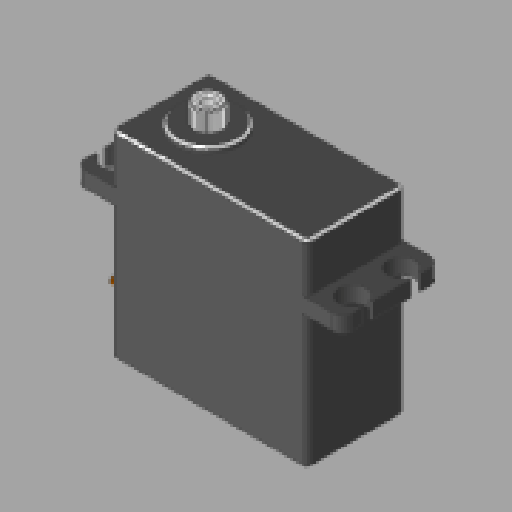
# Autodesk Inventor part: DSC55MG_HipServo
Saved by Autodesk Inventor 2025 (Build 290162000, 162)
## iProperties
Created: 2024-10-08
Part Number: DSC55MG_HipServo
Material: 일반
Document SubType Name: Modeling
Designer: OSB
Density: 2.16623 g/cm^3
Appearance: 기본값
Mass: 72 g
Surface Area: 73.8579 cm^2
Volume: 33.2375 cm^3
Author: OSB
Autodesk Inventor part; units mm, degrees
(part 1 of 2)
ref_plane "YZ Plane" through (0, 0, 0) normal (1, 0, 0) x (0, 1, 0)
ref_plane "XZ Plane" through (0, 0, 0) normal (0, 1, 0) x (-1, 0, 0)
ref_plane "XY Plane" through (0, 0, 0) normal (0, 0, 1) x (1, 0, 0)
sketch "스케치1" plane through (0, 0, 0) normal (0, 1, 0) x (-1, 0, 0)
  line L0 (0, 0) -> (40, 0)
  line L1 (40, 0) -> (40, -20)
  line L2 (40, -20) -> (0, -20)
  line L3 (0, -20) -> (0, 0)
  dimension "d0" = 40
  dimension "d1" = 20
  constraints: 8 end point, 2 parallel, 1 horizontal, 1 perpendicular
  measures "d0" distance of L1.end L2.end
  measures "d1" distance of L0.end L1.end
extrude "돌출1" add sketch "스케치1" along normal blind 40.5
sketch "스케치2" plane through (0, 40.5, 0) normal (0, 1, 0) x (1, 0, 0)
  line L0 (0, 20) -> (-40, 20) projected
  line L1 (-40, 20) -> (-40, 0) projected
  line L2 (-40, 0) -> (0, 0) projected
  line L3 (0, 0) -> (0, 20) projected
  circle A0 centre (-30.2, 10) radius 3
  circle A1 centre (-30.2, 10) radius 6.5
  point P0 (-40, 10)
  dimension "d4" = 9.8
  dimension "d5" = 6
  dimension "d6" = 13
  constraints: 2 centre point, 1 coincident, 1 horizontal alignment, 1 midpoint
  measures "d4" distance from line of L1 A0.centre
  measures "d5" diameter of A0
  measures "d6" diameter of A1
extrude "돌출2" add sketch "스케치2" along normal blind 1.2 contours A1
extrude "돌출3" add sketch "스케치2" along normal blind 5 contours A0
sketch "스케치3" plane through (-40, 0, 0) normal (0, 0, 1) x (1, 0, 0)
  line L0 (0, 0) -> (40, 0) projected
  line L1 (40, 0) -> (40, 40.5) projected
  line L2 (0, 40.5) -> (40, 40.5) projected
  line L3 (0, 0) -> (0, 40.5) projected
  line L4 (-7.25, 30.5) -> (47.25, 30.5)
  line L5 (47.25, 30.5) -> (47.25, 27.3)
  line L6 (47.25, 27.3) -> (-7.25, 27.3)
  line L7 (-7.25, 27.3) -> (-7.25, 30.5)
  line L8 (0, 0) -> (40, 0) projected
  point P0 (20, 0)
  point P1 (20, 0)
  point P2 (40, 30.5)
  point P3 (40, 27.3)
  point P4 (0, 27.3)
  point P5 (0, 30.5)
  dimension "d11" = 27.3
  dimension "d12" = 3.2
  dimension "d13" = 27.25
  dimension "d14" = 27.25
  constraints: 8 end point, 2 midpoint, 2 parallel, 1 horizontal, 1 perpendicular
  measures "d11" distance between parallel lines of L0 L6
  measures "d12" distance between parallel lines of L6 L4
  measures "d13" distance from line of point (20, 0) L7
  measures "d14" distance from line of L5 point (20, 0)
extrude "돌출4" add sketch "스케치3" against normal up to surface (20 mm away) contours L6 L7 L4 L3 | L1 L4 L5 L6
sketch "스케치4" plane through (0, 30.5, 0) normal (0, 1, 0) x (1, 0, 0)
  arc A0 (-46.8117, 14) -> (-46.8117, 16) centre (-44.25, 15) ccw
  arc A1 (-46.8117, 4) -> (-46.8117, 6) centre (-44.25, 5) ccw
  arc A2 (6.8117, 6) -> (6.8117, 4) centre (4.25, 5) ccw
  arc A3 (6.8117, 16) -> (6.8117, 14) centre (4.25, 15) ccw
  line L0 (-44.25, 15) -> (-44.25, 5) construction
  line L1 (0, 20) -> (-40, 20) construction
  line L2 (-40, 20) -> (-40, 0) construction
  line L3 (-40, 0) -> (0, 0) construction
  line L4 (0, 0) -> (0, 20) construction
  circle A4 centre (-30.2, 10) radius 6.5 construction
  line L5 (-40, 0) -> (-47.25, 0) projected
  line L6 (7.25, 0) -> (7.25, 20) projected
  line L7 (-47.25, 0) -> (-47.25, 20) projected
  line L8 (7.25, 16) -> (6.8117, 16)
  line L9 (6.8117, 14) -> (7.25, 14)
  line L10 (7.25, 6) -> (6.8117, 6)
  line L11 (6.8117, 4) -> (7.25, 4)
  line L12 (-20, 20) -> (-20, -6.6659) construction
  line L13 (-47.25, 16) -> (-46.8117, 16)
  line L14 (-46.8117, 14) -> (-47.25, 14)
  line L15 (-46.8117, 6) -> (-47.25, 6)
  line L16 (-46.8117, 4) -> (-47.25, 4)
  point P0 (-44.25, 10)
  point P1 (-40, 10)
  dimension "d17" = 5.5
  dimension "d18" = 5.5
  dimension "d19" = 5.5
  dimension "d20" = 5.5
  dimension "d27" = 10
  dimension "d28" = 5
  dimension "d31" = 3
  dimension "d32" = 3
  dimension "d33" = 1
  dimension "d34" = 1
  dimension "d35" = 1
  dimension "d36" = 1
  dimension "d37" = 1
  dimension "d38" = 1
  dimension "d39" = 1
  dimension "d40" = 1
  constraints: 20 end point, 8 point on circle, 8 point on line, 4 centre point, 4 perpendicular, 3 horizontal, 3 midpoint, 2 horizontal alignment, 2 vertical, 2 vertical alignment
  measures "d17" diameter of A0
  measures "d18" diameter of A1
  measures "d19" diameter of A2
  measures "d20" diameter of A3
  measures "d27" distance of L0.end L0.start
  measures "d28" distance from line of L0.end L5
  measures "d31" distance from line of A3.centre L6
  measures "d32" distance from line of L7 L0.start
  measures "d33" distance from line of A3.centre L8
  measures "d34" distance from line of L9 A3.centre
  measures "d35" distance from line of A2.centre L11
  measures "d36" distance from line of A2.centre L10
  measures "d37" distance from line of L0.end L15
  measures "d38" distance from line of L0.end L16
  measures "d39" distance from line of L0.start L14
  measures "d40" distance from line of L0.start L13
extrude "돌출5" cut sketch "스케치4" against normal blind 48.6
fillet "모깎기1" radius 2 4 edges at (-47.25, 28.9, -20) (-47.25, 28.9, 0) (7.25, 28.9, -20) (7.25, 28.9, 0)
sketch "스케치5" plane through (0, 0, -20) normal (0, 0, -1) x (-1, 0, 0)
  line L0 (4.6935, 36.6092) -> (24.6408, 36.6092) construction
  line L1 (24.6408, 36.6092) -> (24.6408, 31.0943) construction
  line L2 (24.6408, 31.0943) -> (4.6935, 31.0943) construction
  line L3 (4.6935, 31.0943) -> (4.6935, 36.6092) construction
  line L4 (2.4641, 24.8755) -> (37.1372, 24.8755) construction
  line L5 (37.1372, 24.8755) -> (37.1372, 10.619) construction
  line L6 (37.1372, 10.619) -> (2.4641, 10.619) construction
  line L7 (2.4641, 10.619) -> (2.4641, 24.8755) construction
  spline S0 degree 2 poles (4.8977, 34.9463) (4.8977, 35.2927) (5.1238, 35.8689) (5.3207, 36.0767) knots 0 0 0 1 2 2 2
  spline S1 degree 2 poles (5.3207, 36.0767) (5.5067, 36.2773) (6.05, 36.4998) (6.3272, 36.4998) knots 0 0 0 1 2 2 2
  spline S2 degree 2 poles (6.3272, 36.4998) (6.6372, 36.4998) (7.1404, 36.2919) (7.3264, 36.095) knots 0 0 0 1 2 2 2
  spline S3 degree 2 poles (7.3264, 36.095) (7.5598, 35.847) (7.815, 35.0447) (7.815, 34.4284) knots 0 0 0 1 2 2 2
  spline S4 degree 2 poles (7.815, 34.4284) (7.815, 33.8705) (7.5634, 32.8713) (7.3191, 32.5395) knots 0 0 0 1 2 2 2
  spline S5 degree 2 poles (7.3191, 32.5395) (7.0602, 32.1894) (6.3308, 31.8211) (5.7984, 31.8211) knots 0 0 0 1 2 2 2
  spline S6 degree 2 poles (5.7984, 31.8211) (5.6781, 31.8211) (5.4046, 31.8466) (5.2879, 31.8831) knots 0 0 0 1 2 2 2
  line L8 (5.2879, 31.8831) -> (5.2879, 32.4629)
  line L9 (5.2879, 32.4629) -> (5.3171, 32.4629)
  spline S7 degree 2 poles (5.3171, 32.4629) (5.3936, 32.4191) (5.7146, 32.3425) (5.8787, 32.3425) knots 0 0 0 1 2 2 2
  spline S8 degree 2 poles (5.8787, 32.3425) (6.4694, 32.3425) (7.144, 33.1229) (7.1915, 33.845) knots 0 0 0 1 2 2 2
  spline S9 degree 2 poles (7.1915, 33.845) (6.9508, 33.6809) (6.5132, 33.5314) (6.2543, 33.5314) knots 0 0 0 1 2 2 2
  spline S10 degree 2 poles (6.2543, 33.5314) (6.0063, 33.5314) (5.5942, 33.6408) (5.3863, 33.7976) knots 0 0 0 1 2 2 2
  spline S11 degree 2 poles (5.3863, 33.7976) (5.1457, 33.9835) (4.8977, 34.5488) (4.8977, 34.9463) knots 0 0 0 1 2 2 2
  spline S12 degree 2 poles (7.206, 34.5634) (7.206, 35.0192) (7.0383, 35.5954) (6.8888, 35.7522) knots 0 0 0 1 2 2 2
  spline S13 degree 2 poles (6.8888, 35.7522) (6.7575, 35.8981) (6.484, 36.0075) (6.3235, 36.0075) knots 0 0 0 1 2 2 2
  spline S14 degree 2 poles (6.3235, 36.0075) (5.9516, 36.0075) (5.5103, 35.475) (5.5103, 34.9718) knots 0 0 0 1 2 2 2
  spline S15 degree 2 poles (5.5103, 34.9718) (5.5103, 34.6874) (5.6562, 34.319) (5.8167, 34.1878) knots 0 0 0 1 2 2 2
  spline S16 degree 2 poles (5.8167, 34.1878) (5.9334, 34.0929) (6.2214, 34.031) (6.3892, 34.031) knots 0 0 0 1 2 2 2
  spline S17 degree 2 poles (6.3892, 34.031) (6.5825, 34.031) (7.0274, 34.1659) (7.1951, 34.2789) knots 0 0 0 1 2 2 2
  spline S18 degree 2 poles (7.1951, 34.2789) (7.1987, 34.3227) (7.206, 34.4722) (7.206, 34.5634) knots 0 0 0 1 2 2 2
  line L10 (9.0622, 31.9086) -> (8.4933, 31.9086)
  line L11 (8.4933, 31.9086) -> (8.4933, 35.2854)
  line L12 (8.4933, 35.2854) -> (9.0622, 35.2854)
  line L13 (9.0622, 35.2854) -> (9.0622, 31.9086)
  line L14 (9.1023, 35.847) -> (8.4569, 35.847)
  line L15 (8.4569, 35.847) -> (8.4569, 36.4378)
  line L16 (8.4569, 36.4378) -> (9.1023, 36.4378)
  line L17 (9.1023, 36.4378) -> (9.1023, 35.847)
  line L18 (13.7263, 31.9086) -> (13.7263, 33.8632)
  spline S19 degree 2 poles (13.7263, 33.8632) (13.7263, 34.0966) (13.6898, 34.4941) (13.6315, 34.6035) knots 0 0 0 1 2 2 2
  spline S20 degree 2 poles (13.6315, 34.6035) (13.5731, 34.7238) (13.3507, 34.8405) (13.1574, 34.8405) knots 0 0 0 1 2 2 2
  spline S21 degree 2 poles (13.1574, 34.8405) (12.9824, 34.8405) (12.5812, 34.6254) (12.3697, 34.4211) knots 0 0 0 1 2 2 2
  spline S22 degree 2 poles (12.3697, 34.4211) (12.3734, 34.3701) (12.3807, 34.2279) (12.3807, 34.1331) knots 0 0 0 1 2 2 2
  line L19 (12.3807, 34.1331) -> (12.3807, 31.9086)
  line L20 (12.3807, 31.9086) -> (11.8118, 31.9086)
  line L21 (11.8118, 31.9086) -> (11.8118, 33.8632)
  spline S23 degree 2 poles (11.8118, 33.8632) (11.8118, 34.0966) (11.7753, 34.4941) (11.717, 34.6035) knots 0 0 0 1 2 2 2
  spline S24 degree 2 poles (11.717, 34.6035) (11.6586, 34.7238) (11.4362, 34.8405) (11.2429, 34.8405) knots 0 0 0 1 2 2 2
  spline S25 degree 2 poles (11.2429, 34.8405) (11.0606, 34.8405) (10.6558, 34.6108) (10.4662, 34.4321) knots 0 0 0 1 2 2 2
  line L22 (10.4662, 34.4321) -> (10.4662, 31.9086)
  line L23 (10.4662, 31.9086) -> (9.8973, 31.9086)
  line L24 (9.8973, 31.9086) -> (9.8973, 35.2854)
  line L25 (9.8973, 35.2854) -> (10.4662, 35.2854)
  line L26 (10.4662, 35.2854) -> (10.4662, 34.9135)
  spline S26 degree 2 poles (10.4662, 34.9135) (10.6886, 35.1359) (11.1262, 35.3802) (11.3888, 35.3802) knots 0 0 0 1 2 2 2
  spline S27 degree 2 poles (11.3888, 35.3802) (11.6878, 35.3802) (12.1509, 35.1067) (12.2713, 34.7968) knots 0 0 0 1 2 2 2
  spline S28 degree 2 poles (12.2713, 34.7968) (12.5302, 35.0848) (13.0188, 35.3802) (13.3033, 35.3802) knots 0 0 0 1 2 2 2
  spline S29 degree 2 poles (13.3033, 35.3802) (13.5221, 35.3802) (13.8795, 35.2453) (14.0107, 35.0921) knots 0 0 0 1 2 2 2
  spline S30 degree 2 poles (14.0107, 35.0921) (14.1457, 34.939) (14.2952, 34.4795) (14.2952, 34.1331) knots 0 0 0 1 2 2 2
  line L27 (14.2952, 34.1331) -> (14.2952, 31.9086)
  line L28 (14.2952, 31.9086) -> (13.7263, 31.9086)
  spline S31 degree 2 poles (17.8689, 33.597) (17.8689, 32.7437) (17.0484, 31.8138) (16.3628, 31.8138) knots 0 0 0 1 2 2 2
  spline S32 degree 2 poles (16.3628, 31.8138) (15.659, 31.8138) (14.8531, 32.7729) (14.8531, 33.597) knots 0 0 0 1 2 2 2
  spline S33 degree 2 poles (14.8531, 33.597) (14.8531, 34.443) (15.6846, 35.3802) (16.3628, 35.3802) knots 0 0 0 1 2 2 2
  spline S34 degree 2 poles (16.3628, 35.3802) (17.0484, 35.3802) (17.8689, 34.4467) (17.8689, 33.597) knots 0 0 0 1 2 2 2
  spline S35 degree 2 poles (17.2818, 33.597) (17.2818, 34.2534) (16.8041, 34.8916) (16.3628, 34.8916) knots 0 0 0 1 2 2 2
  spline S36 degree 2 poles (16.3628, 34.8916) (15.9216, 34.8916) (15.4402, 34.2534) (15.4402, 33.597) knots 0 0 0 1 2 2 2
  spline S37 degree 2 poles (15.4402, 33.597) (15.4402, 32.9588) (15.9216, 32.3024) (16.3628, 32.3024) knots 0 0 0 1 2 2 2
  spline S38 degree 2 poles (16.3628, 32.3024) (16.8004, 32.3024) (17.2818, 32.9479) (17.2818, 33.597) knots 0 0 0 1 2 2 2
  line L29 (21.0488, 31.9086) -> (20.4799, 31.9086)
  line L30 (20.4799, 31.9086) -> (20.4799, 32.2514)
  spline S39 degree 2 poles (20.4799, 32.2514) (20.3487, 32.142) (20.1554, 31.9961) (20.0241, 31.9341) knots 0 0 0 1 2 2 2
  spline S40 degree 2 poles (20.0241, 31.9341) (19.9038, 31.8758) (19.6449, 31.8138) (19.4735, 31.8138) knots 0 0 0 1 2 2 2
  spline S41 degree 2 poles (19.4735, 31.8138) (19.1963, 31.8138) (18.7295, 32.0435) (18.5654, 32.266) knots 0 0 0 1 2 2 2
  spline S42 degree 2 poles (18.5654, 32.266) (18.4013, 32.4884) (18.219, 33.1448) (18.219, 33.5715) knots 0 0 0 1 2 2 2
  spline S43 degree 2 poles (18.219, 33.5715) (18.219, 34.0164) (18.4487, 34.6655) (18.6493, 34.9098) knots 0 0 0 1 2 2 2
  spline S44 degree 2 poles (18.6493, 34.9098) (18.8353, 35.1286) (19.3568, 35.3802) (19.6449, 35.3802) knots 0 0 0 1 2 2 2
  spline S45 degree 2 poles (19.6449, 35.3802) (19.8965, 35.3802) (20.2721, 35.2672) (20.4799, 35.1505) knots 0 0 0 1 2 2 2
  line L31 (20.4799, 35.1505) -> (20.4799, 36.6092)
  line L32 (20.4799, 36.6092) -> (21.0488, 36.6092)
  line L33 (21.0488, 36.6092) -> (21.0488, 31.9086)
  line L34 (20.4799, 32.7291) -> (20.4799, 34.6801)
  spline S46 degree 2 poles (20.4799, 34.6801) (20.2684, 34.7822) (19.9329, 34.8588) (19.7397, 34.8588) knots 0 0 0 1 2 2 2
  spline S47 degree 2 poles (19.7397, 34.8588) (19.3021, 34.8588) (18.8061, 34.2023) (18.8061, 33.5824) knots 0 0 0 1 2 2 2
  spline S48 degree 2 poles (18.8061, 33.5824) (18.8061, 32.9844) (19.1854, 32.3535) (19.6047, 32.3535) knots 0 0 0 1 2 2 2
  spline S49 degree 2 poles (19.6047, 32.3535) (19.8272, 32.3535) (20.2794, 32.5577) (20.4799, 32.7291) knots 0 0 0 1 2 2 2
  spline S50 degree 2 poles (9.255, 17.8738) (9.255, 17.1526) (8.7931, 15.9208) (8.3717, 15.467) knots 0 0 0 1 2 2 2
  spline S51 degree 2 poles (8.3717, 15.467) (7.9503, 15.0132) (6.6942, 14.4865) (5.9163, 14.4865) knots 0 0 0 1 2 2 2
  spline S52 degree 2 poles (5.9163, 14.4865) (5.2031, 14.4865) (3.8093, 14.8025) (3.2988, 15.0537) knots 0 0 0 1 2 2 2
  line L35 (3.2988, 15.0537) -> (3.2988, 16.4719)
  line L36 (3.2988, 16.4719) -> (3.396, 16.4719)
  spline S53 degree 2 poles (3.396, 16.4719) (3.55, 16.3584) (4.1253, 16.0667) (4.4738, 15.937) knots 0 0 0 1 2 2 2
  spline S54 degree 2 poles (4.4738, 15.937) (4.8709, 15.7993) (5.5273, 15.6453) (5.9406, 15.6453) knots 0 0 0 1 2 2 2
  spline S55 degree 2 poles (5.9406, 15.6453) (6.3458, 15.6453) (7.1075, 15.937) (7.383, 16.2531) knots 0 0 0 1 2 2 2
  spline S56 degree 2 poles (7.383, 16.2531) (7.6343, 16.5529) (7.8936, 17.3471) (7.8936, 17.8819) knots 0 0 0 1 2 2 2
  spline S57 degree 2 poles (7.8936, 17.8819) (7.8936, 18.4168) (7.6018, 19.0975) (7.3263, 19.3244) knots 0 0 0 1 2 2 2
  spline S58 degree 2 poles (7.3263, 19.3244) (7.0427, 19.5756) (6.1999, 19.7863) (5.6894, 19.7863) knots 0 0 0 1 2 2 2
  spline S59 degree 2 poles (5.6894, 19.7863) (5.1383, 19.7863) (4.0443, 19.6161) (3.7121, 19.5432) knots 0 0 0 1 2 2 2
  line L37 (3.7121, 19.5432) -> (3.7121, 24.6972)
  line L38 (3.7121, 24.6972) -> (9.1983, 24.6972)
  line L39 (9.1983, 24.6972) -> (9.1983, 23.5221)
  line L40 (9.1983, 23.5221) -> (5.0005, 23.5221)
  line L41 (5.0005, 23.5221) -> (5.0005, 20.856)
  spline S60 degree 2 poles (5.0005, 20.856) (5.2437, 20.8884) (5.7137, 20.9127) (5.9082, 20.9127) knots 0 0 0 1 2 2 2
  spline S61 degree 2 poles (5.9082, 20.9127) (6.678, 20.9127) (7.7396, 20.6615) (8.2258, 20.2887) knots 0 0 0 1 2 2 2
  spline S62 degree 2 poles (8.2258, 20.2887) (8.7202, 19.916) (9.255, 18.7814) (9.255, 17.8738) knots 0 0 0 1 2 2 2
  spline S63 degree 2 poles (16.7591, 17.8738) (16.7591, 17.1526) (16.2971, 15.9208) (15.8757, 15.467) knots 0 0 0 1 2 2 2
  spline S64 degree 2 poles (15.8757, 15.467) (15.4544, 15.0132) (14.1983, 14.4865) (13.4203, 14.4865) knots 0 0 0 1 2 2 2
  spline S65 degree 2 poles (13.4203, 14.4865) (12.7072, 14.4865) (11.3133, 14.8025) (10.8028, 15.0537) knots 0 0 0 1 2 2 2
  line L42 (10.8028, 15.0537) -> (10.8028, 16.4719)
  line L43 (10.8028, 16.4719) -> (10.9001, 16.4719)
  spline S66 degree 2 poles (10.9001, 16.4719) (11.054, 16.3584) (11.6294, 16.0667) (11.9779, 15.937) knots 0 0 0 1 2 2 2
  spline S67 degree 2 poles (11.9779, 15.937) (12.3749, 15.7993) (13.0313, 15.6453) (13.4446, 15.6453) knots 0 0 0 1 2 2 2
  spline S68 degree 2 poles (13.4446, 15.6453) (13.8498, 15.6453) (14.6116, 15.937) (14.8871, 16.2531) knots 0 0 0 1 2 2 2
  spline S69 degree 2 poles (14.8871, 16.2531) (15.1383, 16.5529) (15.3976, 17.3471) (15.3976, 17.8819) knots 0 0 0 1 2 2 2
  spline S70 degree 2 poles (15.3976, 17.8819) (15.3976, 18.4168) (15.1059, 19.0975) (14.8304, 19.3244) knots 0 0 0 1 2 2 2
  spline S71 degree 2 poles (14.8304, 19.3244) (14.5467, 19.5756) (13.7039, 19.7863) (13.1934, 19.7863) knots 0 0 0 1 2 2 2
  spline S72 degree 2 poles (13.1934, 19.7863) (12.6424, 19.7863) (11.5484, 19.6161) (11.2161, 19.5432) knots 0 0 0 1 2 2 2
  line L44 (11.2161, 19.5432) -> (11.2161, 24.6972)
  line L45 (11.2161, 24.6972) -> (16.7023, 24.6972)
  line L46 (16.7023, 24.6972) -> (16.7023, 23.5221)
  line L47 (16.7023, 23.5221) -> (12.5046, 23.5221)
  line L48 (12.5046, 23.5221) -> (12.5046, 20.856)
  spline S73 degree 2 poles (12.5046, 20.856) (12.7477, 20.8884) (13.2177, 20.9127) (13.4122, 20.9127) knots 0 0 0 1 2 2 2
  spline S74 degree 2 poles (13.4122, 20.9127) (14.1821, 20.9127) (15.2437, 20.6615) (15.7299, 20.2887) knots 0 0 0 1 2 2 2
  spline S75 degree 2 poles (15.7299, 20.2887) (16.2242, 19.916) (16.7591, 18.7814) (16.7591, 17.8738) knots 0 0 0 1 2 2 2
  line L49 (25.7785, 14.6972) -> (24.0524, 14.6972)
  line L50 (24.0524, 14.6972) -> (20.3976, 19.3487)
  line L51 (20.3976, 19.3487) -> (19.8142, 18.6923)
  line L52 (19.8142, 18.6923) -> (19.8142, 14.6972)
  line L53 (19.8142, 14.6972) -> (18.4851, 14.6972)
  line L54 (18.4851, 14.6972) -> (18.4851, 24.6972)
  line L55 (18.4851, 24.6972) -> (19.8142, 24.6972)
  line L56 (19.8142, 24.6972) -> (19.8142, 20.1024)
  line L57 (19.8142, 20.1024) -> (23.9146, 24.6972)
  line L58 (23.9146, 24.6972) -> (25.5354, 24.6972)
  line L59 (25.5354, 24.6972) -> (21.3944, 20.232)
  line L60 (21.3944, 20.232) -> (25.7785, 14.6972)
  spline S76 degree 2 poles (30.7623, 14.5027) (29.7007, 14.5027) (27.9422, 15.151) (27.3101, 15.8074) knots 0 0 0 1 2 2 2
  spline S77 degree 2 poles (27.3101, 15.8074) (26.678, 16.4719) (26.0054, 18.433) (26.0054, 19.7053) knots 0 0 0 1 2 2 2
  spline S78 degree 2 poles (26.0054, 19.7053) (26.0054, 20.9127) (26.6861, 22.8252) (27.3182, 23.5059) knots 0 0 0 1 2 2 2
  spline S79 degree 2 poles (27.3182, 23.5059) (27.926, 24.1623) (29.7088, 24.8755) (30.7704, 24.8755) knots 0 0 0 1 2 2 2
  spline S80 degree 2 poles (30.7704, 24.8755) (31.2809, 24.8755) (32.2048, 24.7296) (32.6262, 24.5999) knots 0 0 0 1 2 2 2
  spline S81 degree 2 poles (32.6262, 24.5999) (32.9665, 24.5027) (33.7931, 24.1461) (34.0443, 24.0165) knots 0 0 0 1 2 2 2
  line L61 (34.0443, 24.0165) -> (34.0443, 22.4119)
  line L62 (34.0443, 22.4119) -> (33.9309, 22.4119)
  spline S82 degree 2 poles (33.9309, 22.4119) (33.6796, 22.6307) (33.1529, 23.0278) (32.6667, 23.2547) knots 0 0 0 1 2 2 2
  spline S83 degree 2 poles (32.6667, 23.2547) (32.2615, 23.4573) (31.2161, 23.7247) (30.6164, 23.7247) knots 0 0 0 1 2 2 2
  spline S84 degree 2 poles (30.6164, 23.7247) (29.174, 23.7247) (27.3911, 21.5529) (27.3911, 19.7458) knots 0 0 0 1 2 2 2
  spline S85 degree 2 poles (27.3911, 19.7458) (27.3911, 18.7409) (27.8612, 17.2336) (28.3069, 16.715) knots 0 0 0 1 2 2 2
  spline S86 degree 2 poles (28.3069, 16.715) (28.7364, 16.1964) (29.9519, 15.6534) (30.7137, 15.6534) knots 0 0 0 1 2 2 2
  spline S87 degree 2 poles (30.7137, 15.6534) (31.2728, 15.6534) (32.3911, 15.8155) (32.772, 15.9776) knots 0 0 0 1 2 2 2
  line L63 (32.772, 15.9776) -> (32.772, 18.5626)
  line L64 (32.772, 18.5626) -> (30.4544, 18.5626)
  line L65 (30.4544, 18.5626) -> (30.4544, 19.7296)
  line L66 (30.4544, 19.7296) -> (34.0848, 19.7296)
  line L67 (34.0848, 19.7296) -> (34.0848, 15.3617)
  spline S88 degree 2 poles (34.0848, 15.3617) (33.8336, 15.2482) (32.9746, 14.8998) (32.6099, 14.7944) knots 0 0 0 1 2 2 2
  spline S89 degree 2 poles (32.6099, 14.7944) (32.1156, 14.6485) (31.3215, 14.5027) (30.7623, 14.5027) knots 0 0 0 1 2 2 2
  spline S90 degree 2 poles (3.6938, 7.6422) (3.4507, 7.6422) (3.0394, 7.8063) (2.8895, 7.9704) knots 0 0 0 1 2 2 2
  spline S91 degree 2 poles (2.8895, 7.9704) (2.7396, 8.1325) (2.5755, 8.6187) (2.5755, 8.9348) knots 0 0 0 1 2 2 2
  spline S92 degree 2 poles (2.5755, 8.9348) (2.5755, 9.2488) (2.7356, 9.7147) (2.8875, 9.8869) knots 0 0 0 1 2 2 2
  spline S93 degree 2 poles (2.8875, 9.8869) (3.0374, 10.0551) (3.4467, 10.2313) (3.6999, 10.2313) knots 0 0 0 1 2 2 2
  spline S94 degree 2 poles (3.6999, 10.2313) (3.8255, 10.2313) (4.0463, 10.1949) (4.1395, 10.1665) knots 0 0 0 1 2 2 2
  spline S95 degree 2 poles (4.1395, 10.1665) (4.2206, 10.1402) (4.3887, 10.0652) (4.4718, 10.0206) knots 0 0 0 1 2 2 2
  line L68 (4.4718, 10.0206) -> (4.4718, 9.6195)
  line L69 (4.4718, 9.6195) -> (4.4454, 9.6195)
  spline S96 degree 2 poles (4.4454, 9.6195) (4.4009, 9.66) (4.2631, 9.7735) (4.1638, 9.8282) knots 0 0 0 1 2 2 2
  spline S97 degree 2 poles (4.1638, 9.8282) (4.0686, 9.8809) (3.8437, 9.9477) (3.6979, 9.9477) knots 0 0 0 1 2 2 2
  spline S98 degree 2 poles (3.6979, 9.9477) (3.5378, 9.9477) (3.2522, 9.816) (3.1448, 9.6904) knots 0 0 0 1 2 2 2
  spline S99 degree 2 poles (3.1448, 9.6904) (3.0394, 9.5628) (2.9219, 9.1758) (2.9219, 8.9348) knots 0 0 0 1 2 2 2
  spline S100 degree 2 poles (2.9219, 8.9348) (2.9219, 8.6775) (3.0455, 8.3067) (3.1529, 8.1791) knots 0 0 0 1 2 2 2
  spline S101 degree 2 poles (3.1529, 8.1791) (3.2582, 8.0555) (3.5398, 7.9299) (3.6979, 7.9299) knots 0 0 0 1 2 2 2
  spline S102 degree 2 poles (3.6979, 7.9299) (3.8417, 7.9299) (4.0868, 8.0008) (4.1821, 8.0535) knots 0 0 0 1 2 2 2
  spline S103 degree 2 poles (4.1821, 8.0535) (4.2732, 8.1061) (4.409, 8.2155) (4.4475, 8.254) knots 0 0 0 1 2 2 2
  line L70 (4.4475, 8.254) -> (4.4718, 8.254)
  line L71 (4.4718, 8.254) -> (4.4718, 7.857)
  spline S104 degree 2 poles (4.4718, 7.857) (4.3887, 7.8185) (4.2428, 7.7476) (4.1395, 7.7151) knots 0 0 0 1 2 2 2
  spline S105 degree 2 poles (4.1395, 7.7151) (4.0301, 7.6787) (3.8437, 7.6422) (3.6938, 7.6422) knots 0 0 0 1 2 2 2
  spline S106 degree 2 poles (6.5504, 9.9011) (6.6922, 9.735) (6.8502, 9.2488) (6.8502, 8.9368) knots 0 0 0 1 2 2 2
  spline S107 degree 2 poles (6.8502, 8.9368) (6.8502, 8.6329) (6.6962, 8.1406) (6.5504, 7.9745) knots 0 0 0 1 2 2 2
  spline S108 degree 2 poles (6.5504, 7.9745) (6.3964, 7.8002) (5.9892, 7.6341) (5.7441, 7.6341) knots 0 0 0 1 2 2 2
  spline S109 degree 2 poles (5.7441, 7.6341) (5.4908, 7.6341) (5.0856, 7.8063) (4.9377, 7.9745) knots 0 0 0 1 2 2 2
  spline S110 degree 2 poles (4.9377, 7.9745) (4.7939, 8.1406) (4.6399, 8.6288) (4.6399, 8.9368) knots 0 0 0 1 2 2 2
  spline S111 degree 2 poles (4.6399, 8.9368) (4.6399, 9.2508) (4.7959, 9.7289) (4.9398, 9.9011) knots 0 0 0 1 2 2 2
  spline S112 degree 2 poles (4.9398, 9.9011) (5.0856, 10.0672) (5.4928, 10.2395) (5.7441, 10.2395) knots 0 0 0 1 2 2 2
  spline S113 degree 2 poles (5.7441, 10.2395) (5.9993, 10.2395) (6.4086, 10.0612) (6.5504, 9.9011) knots 0 0 0 1 2 2 2
  spline S114 degree 2 poles (6.5038, 8.9368) (6.5038, 9.1839) (6.3964, 9.5668) (6.2992, 9.6924) knots 0 0 0 1 2 2 2
  spline S115 degree 2 poles (6.2992, 9.6924) (6.1999, 9.8221) (5.9203, 9.9518) (5.7461, 9.9518) knots 0 0 0 1 2 2 2
  spline S116 degree 2 poles (5.7461, 9.9518) (5.5658, 9.9518) (5.2943, 9.8262) (5.191, 9.6924) knots 0 0 0 1 2 2 2
  spline S117 degree 2 poles (5.191, 9.6924) (5.0917, 9.5648) (4.9864, 9.1799) (4.9864, 8.9368) knots 0 0 0 1 2 2 2
  spline S118 degree 2 poles (4.9864, 8.9368) (4.9864, 8.4445) (5.3997, 7.9218) (5.7461, 7.9218) knots 0 0 0 1 2 2 2
  spline S119 degree 2 poles (5.7461, 7.9218) (6.0925, 7.9218) (6.5038, 8.4445) (6.5038, 8.9368) knots 0 0 0 1 2 2 2
  line L72 (9.1497, 7.6868) -> (8.7181, 7.6868)
  line L73 (8.7181, 7.6868) -> (7.928, 8.6815)
  line L74 (7.928, 8.6815) -> (7.5471, 8.6815)
  line L75 (7.5471, 8.6815) -> (7.5471, 7.6868)
  line L76 (7.5471, 7.6868) -> (7.2149, 7.6868)
  line L77 (7.2149, 7.6868) -> (7.2149, 10.1868)
  line L78 (7.2149, 10.1868) -> (7.8591, 10.1868)
  spline S120 degree 2 poles (7.8591, 10.1868) (8.0739, 10.1868) (8.3636, 10.1402) (8.4953, 10.0551) knots 0 0 0 1 2 2 2
  spline S121 degree 2 poles (8.4953, 10.0551) (8.627, 9.97) (8.7789, 9.7046) (8.7789, 9.5081) knots 0 0 0 1 2 2 2
  spline S122 degree 2 poles (8.7789, 9.5081) (8.7789, 9.2346) (8.4993, 8.8638) (8.2603, 8.7747) knots 0 0 0 1 2 2 2
  line L79 (8.2603, 8.7747) -> (9.1497, 7.6868)
  spline S123 degree 2 poles (8.4325, 9.4818) (8.4325, 9.5912) (8.3555, 9.7593) (8.2744, 9.814) knots 0 0 0 1 2 2 2
  spline S124 degree 2 poles (8.2744, 9.814) (8.2035, 9.8606) (8.0151, 9.8991) (7.8774, 9.8991) knots 0 0 0 1 2 2 2
  line L80 (7.8774, 9.8991) -> (7.5471, 9.8991)
  line L81 (7.5471, 9.8991) -> (7.5471, 8.9591)
  line L82 (7.5471, 8.9591) -> (7.8389, 8.9591)
  spline S125 degree 2 poles (7.8389, 8.9591) (7.9827, 8.9591) (8.2116, 9.0097) (8.2907, 9.0887) knots 0 0 0 1 2 2 2
  spline S126 degree 2 poles (8.2907, 9.0887) (8.3636, 9.1576) (8.4325, 9.3521) (8.4325, 9.4818) knots 0 0 0 1 2 2 2
  line L83 (9.3482, 7.6868) -> (9.3482, 10.1868)
  line L84 (9.3482, 10.1868) -> (10.9122, 10.1868)
  line L85 (10.9122, 10.1868) -> (10.9122, 9.891)
  line L86 (10.9122, 9.891) -> (9.6804, 9.891)
  line L87 (9.6804, 9.891) -> (9.6804, 9.2062)
  line L88 (9.6804, 9.2062) -> (10.8291, 9.2062)
  line L89 (10.8291, 9.2062) -> (10.8291, 8.9104)
  line L90 (10.8291, 8.9104) -> (9.6804, 8.9104)
  line L91 (9.6804, 8.9104) -> (9.6804, 7.9826)
  line L92 (9.6804, 7.9826) -> (10.9122, 7.9826)
  line L93 (10.9122, 7.9826) -> (10.9122, 7.6868)
  line L94 (10.9122, 7.6868) -> (9.3482, 7.6868)
  line L95 (12.7254, 7.6868) -> (11.2769, 7.6868)
  line L96 (11.2769, 7.6868) -> (11.2769, 10.1868)
  line L97 (11.2769, 10.1868) -> (11.6091, 10.1868)
  line L98 (11.6091, 10.1868) -> (11.6091, 7.9826)
  line L99 (11.6091, 7.9826) -> (12.7254, 7.9826)
  line L100 (12.7254, 7.9826) -> (12.7254, 7.6868)
  line L101 (12.9868, 7.6868) -> (12.9868, 10.1868)
  line L102 (12.9868, 10.1868) -> (14.5508, 10.1868)
  line L103 (14.5508, 10.1868) -> (14.5508, 9.891)
  line L104 (14.5508, 9.891) -> (13.319, 9.891)
  line L105 (13.319, 9.891) -> (13.319, 9.2062)
  line L106 (13.319, 9.2062) -> (14.4677, 9.2062)
  line L107 (14.4677, 9.2062) -> (14.4677, 8.9104)
  line L108 (14.4677, 8.9104) -> (13.319, 8.9104)
  line L109 (13.319, 8.9104) -> (13.319, 7.9826)
  line L110 (13.319, 7.9826) -> (14.5508, 7.9826)
  line L111 (14.5508, 7.9826) -> (14.5508, 7.6868)
  line L112 (14.5508, 7.6868) -> (12.9868, 7.6868)
  spline S127 degree 2 poles (15.6124, 7.6422) (15.3409, 7.6422) (14.96, 7.7557) (14.7919, 7.8367) knots 0 0 0 1 2 2 2
  line L113 (14.7919, 7.8367) -> (14.7919, 8.254)
  line L114 (14.7919, 8.254) -> (14.8162, 8.254)
  spline S128 degree 2 poles (14.8162, 8.254) (14.9803, 8.1001) (15.3956, 7.9299) (15.5881, 7.9299) knots 0 0 0 1 2 2 2
  spline S129 degree 2 poles (15.5881, 7.9299) (15.8636, 7.9299) (16.1452, 8.1588) (16.1452, 8.3472) knots 0 0 0 1 2 2 2
  spline S130 degree 2 poles (16.1452, 8.3472) (16.1452, 8.4971) (15.9973, 8.6835) (15.8373, 8.7301) knots 0 0 0 1 2 2 2
  spline S131 degree 2 poles (15.8373, 8.7301) (15.7218, 8.7625) (15.5293, 8.8071) (15.3855, 8.8436) knots 0 0 0 1 2 2 2
  spline S132 degree 2 poles (15.3855, 8.8436) (15.2558, 8.878) (15.0512, 8.9813) (14.9722, 9.0644) knots 0 0 0 1 2 2 2
  spline S133 degree 2 poles (14.9722, 9.0644) (14.8952, 9.1475) (14.8101, 9.3703) (14.8101, 9.5162) knots 0 0 0 1 2 2 2
  spline S134 degree 2 poles (14.8101, 9.5162) (14.8101, 9.8201) (15.2842, 10.2313) (15.6509, 10.2313) knots 0 0 0 1 2 2 2
  spline S135 degree 2 poles (15.6509, 10.2313) (15.8616, 10.2313) (16.2343, 10.1483) (16.3944, 10.0693) knots 0 0 0 1 2 2 2
  line L115 (16.3944, 10.0693) -> (16.3944, 9.6722)
  line L116 (16.3944, 9.6722) -> (16.3701, 9.6722)
  spline S136 degree 2 poles (16.3701, 9.6722) (16.2505, 9.7816) (15.8778, 9.9437) (15.6732, 9.9437) knots 0 0 0 1 2 2 2
  spline S137 degree 2 poles (15.6732, 9.9437) (15.4422, 9.9437) (15.1565, 9.7269) (15.1565, 9.5506) knots 0 0 0 1 2 2 2
  spline S138 degree 2 poles (15.1565, 9.5506) (15.1565, 9.3926) (15.3247, 9.2042) (15.4827, 9.1617) knots 0 0 0 1 2 2 2
  spline S139 degree 2 poles (15.4827, 9.1617) (15.5881, 9.1333) (15.894, 9.0604) (15.9953, 9.03) knots 0 0 0 1 2 2 2
  spline S140 degree 2 poles (15.9953, 9.03) (16.2526, 8.951) (16.4916, 8.6329) (16.4916, 8.3999) knots 0 0 0 1 2 2 2
  spline S141 degree 2 poles (16.4916, 8.3999) (16.4916, 8.252) (16.3721, 7.9684) (16.2647, 7.8691) knots 0 0 0 1 2 2 2
  spline S142 degree 2 poles (16.2647, 7.8691) (16.1452, 7.7597) (15.8413, 7.6422) (15.6124, 7.6422) knots 0 0 0 1 2 2 2
  spline S143 degree 2 poles (17.5269, 7.6422) (17.2554, 7.6422) (16.8745, 7.7557) (16.7064, 7.8367) knots 0 0 0 1 2 2 2
  line L117 (16.7064, 7.8367) -> (16.7064, 8.254)
  line L118 (16.7064, 8.254) -> (16.7307, 8.254)
  spline S144 degree 2 poles (16.7307, 8.254) (16.8948, 8.1001) (17.3101, 7.9299) (17.5026, 7.9299) knots 0 0 0 1 2 2 2
  spline S145 degree 2 poles (17.5026, 7.9299) (17.7781, 7.9299) (18.0597, 8.1588) (18.0597, 8.3472) knots 0 0 0 1 2 2 2
  spline S146 degree 2 poles (18.0597, 8.3472) (18.0597, 8.4971) (17.9118, 8.6835) (17.7518, 8.7301) knots 0 0 0 1 2 2 2
  spline S147 degree 2 poles (17.7518, 8.7301) (17.6363, 8.7625) (17.4438, 8.8071) (17.3, 8.8436) knots 0 0 0 1 2 2 2
  spline S148 degree 2 poles (17.3, 8.8436) (17.1703, 8.878) (16.9657, 8.9813) (16.8867, 9.0644) knots 0 0 0 1 2 2 2
  spline S149 degree 2 poles (16.8867, 9.0644) (16.8097, 9.1475) (16.7246, 9.3703) (16.7246, 9.5162) knots 0 0 0 1 2 2 2
  spline S150 degree 2 poles (16.7246, 9.5162) (16.7246, 9.8201) (17.1987, 10.2313) (17.5654, 10.2313) knots 0 0 0 1 2 2 2
  spline S151 degree 2 poles (17.5654, 10.2313) (17.7761, 10.2313) (18.1488, 10.1483) (18.3089, 10.0693) knots 0 0 0 1 2 2 2
  line L119 (18.3089, 10.0693) -> (18.3089, 9.6722)
  line L120 (18.3089, 9.6722) -> (18.2846, 9.6722)
  spline S152 degree 2 poles (18.2846, 9.6722) (18.165, 9.7816) (17.7923, 9.9437) (17.5877, 9.9437) knots 0 0 0 1 2 2 2
  spline S153 degree 2 poles (17.5877, 9.9437) (17.3567, 9.9437) (17.071, 9.7269) (17.071, 9.5506) knots 0 0 0 1 2 2 2
  spline S154 degree 2 poles (17.071, 9.5506) (17.071, 9.3926) (17.2392, 9.2042) (17.3972, 9.1617) knots 0 0 0 1 2 2 2
  spline S155 degree 2 poles (17.3972, 9.1617) (17.5026, 9.1333) (17.8085, 9.0604) (17.9098, 9.03) knots 0 0 0 1 2 2 2
  spline S156 degree 2 poles (17.9098, 9.03) (18.1671, 8.951) (18.4061, 8.6329) (18.4061, 8.3999) knots 0 0 0 1 2 2 2
  spline S157 degree 2 poles (18.4061, 8.3999) (18.4061, 8.252) (18.2866, 7.9684) (18.1792, 7.8691) knots 0 0 0 1 2 2 2
  spline S158 degree 2 poles (18.1792, 7.8691) (18.0597, 7.7597) (17.7558, 7.6422) (17.5269, 7.6422) knots 0 0 0 1 2 2 2
  spline S159 degree 2 poles (4.6886, 4.8186) (4.6886, 4.4762) (4.411, 3.9251) (4.178, 3.7712) knots 0 0 0 1 2 2 2
  spline S160 degree 2 poles (4.178, 3.7712) (3.9876, 3.6516) (3.5966, 3.5706) (3.2927, 3.5706) knots 0 0 0 1 2 2 2
  line L121 (3.2927, 3.5706) -> (2.7173, 3.5706)
  line L122 (2.7173, 3.5706) -> (2.7173, 6.0706)
  line L123 (2.7173, 6.0706) -> (3.2866, 6.0706)
  spline S161 degree 2 poles (3.2866, 6.0706) (3.6391, 6.0706) (4.0403, 5.9652) (4.1821, 5.8721) knots 0 0 0 1 2 2 2
  spline S162 degree 2 poles (4.1821, 5.8721) (4.4232, 5.712) (4.6886, 5.1832) (4.6886, 4.8186) knots 0 0 0 1 2 2 2
  spline S163 degree 2 poles (4.3421, 4.8226) (4.3421, 5.1103) (4.1517, 5.5175) (3.9633, 5.633) knots 0 0 0 1 2 2 2
  spline S164 degree 2 poles (3.9633, 5.633) (3.8296, 5.712) (3.5277, 5.7829) (3.3028, 5.7829) knots 0 0 0 1 2 2 2
  line L124 (3.3028, 5.7829) -> (3.0496, 5.7829)
  line L125 (3.0496, 5.7829) -> (3.0496, 3.8583)
  line L126 (3.0496, 3.8583) -> (3.3028, 3.8583)
  spline S165 degree 2 poles (3.3028, 3.8583) (3.5236, 3.8583) (3.8579, 3.9292) (3.9937, 4.0244) knots 0 0 0 1 2 2 2
  spline S166 degree 2 poles (3.9937, 4.0244) (4.1679, 4.1419) (4.3421, 4.5309) (4.3421, 4.8226) knots 0 0 0 1 2 2 2
  line L127 (5.9203, 3.5706) -> (4.9519, 3.5706)
  line L128 (4.9519, 3.5706) -> (4.9519, 3.8259)
  line L129 (4.9519, 3.8259) -> (5.27, 3.8259)
  line L130 (5.27, 3.8259) -> (5.27, 5.8153)
  line L131 (5.27, 5.8153) -> (4.9519, 5.8153)
  line L132 (4.9519, 5.8153) -> (4.9519, 6.0706)
  line L133 (4.9519, 6.0706) -> (5.9203, 6.0706)
  line L134 (5.9203, 6.0706) -> (5.9203, 5.8153)
  line L135 (5.9203, 5.8153) -> (5.6022, 5.8153)
  line L136 (5.6022, 5.8153) -> (5.6022, 3.8259)
  line L137 (5.6022, 3.8259) -> (5.9203, 3.8259)
  line L138 (5.9203, 3.8259) -> (5.9203, 3.5706)
  spline S167 degree 2 poles (7.379, 3.522) (7.1136, 3.522) (6.674, 3.684) (6.5159, 3.8481) knots 0 0 0 1 2 2 2
  spline S168 degree 2 poles (6.5159, 3.8481) (6.3579, 4.0143) (6.1898, 4.5045) (6.1898, 4.8226) knots 0 0 0 1 2 2 2
  spline S169 degree 2 poles (6.1898, 4.8226) (6.1898, 5.1245) (6.3599, 5.6026) (6.518, 5.7728) knots 0 0 0 1 2 2 2
  spline S170 degree 2 poles (6.518, 5.7728) (6.6699, 5.9369) (7.1156, 6.1152) (7.381, 6.1152) knots 0 0 0 1 2 2 2
  spline S171 degree 2 poles (7.381, 6.1152) (7.5086, 6.1152) (7.7396, 6.0787) (7.845, 6.0463) knots 0 0 0 1 2 2 2
  spline S172 degree 2 poles (7.845, 6.0463) (7.93, 6.022) (8.1367, 5.9328) (8.1995, 5.9004) knots 0 0 0 1 2 2 2
  line L139 (8.1995, 5.9004) -> (8.1995, 5.4993)
  line L140 (8.1995, 5.4993) -> (8.1711, 5.4993)
  spline S173 degree 2 poles (8.1711, 5.4993) (8.1083, 5.554) (7.9766, 5.6532) (7.8551, 5.71) knots 0 0 0 1 2 2 2
  spline S174 degree 2 poles (7.8551, 5.71) (7.7538, 5.7606) (7.4924, 5.8275) (7.3425, 5.8275) knots 0 0 0 1 2 2 2
  spline S175 degree 2 poles (7.3425, 5.8275) (6.9819, 5.8275) (6.5362, 5.2845) (6.5362, 4.8327) knots 0 0 0 1 2 2 2
  spline S176 degree 2 poles (6.5362, 4.8327) (6.5362, 4.5815) (6.6537, 4.2047) (6.7651, 4.075) knots 0 0 0 1 2 2 2
  spline S177 degree 2 poles (6.7651, 4.075) (6.8725, 3.9454) (7.1764, 3.8097) (7.3668, 3.8097) knots 0 0 0 1 2 2 2
  spline S178 degree 2 poles (7.3668, 3.8097) (7.5066, 3.8097) (7.7862, 3.8502) (7.8814, 3.8907) knots 0 0 0 1 2 2 2
  line L141 (7.8814, 3.8907) -> (7.8814, 4.537)
  line L142 (7.8814, 4.537) -> (7.302, 4.537)
  line L143 (7.302, 4.537) -> (7.302, 4.8287)
  line L144 (7.302, 4.8287) -> (8.2096, 4.8287)
  line L145 (8.2096, 4.8287) -> (8.2096, 3.7367)
  spline S179 degree 2 poles (8.2096, 3.7367) (8.1468, 3.7084) (7.9321, 3.6212) (7.8409, 3.5949) knots 0 0 0 1 2 2 2
  spline S180 degree 2 poles (7.8409, 3.5949) (7.7173, 3.5584) (7.5188, 3.522) (7.379, 3.522) knots 0 0 0 1 2 2 2
  line L146 (9.4981, 3.5706) -> (8.5297, 3.5706)
  line L147 (8.5297, 3.5706) -> (8.5297, 3.8259)
  line L148 (8.5297, 3.8259) -> (8.8478, 3.8259)
  line L149 (8.8478, 3.8259) -> (8.8478, 5.8153)
  line L150 (8.8478, 5.8153) -> (8.5297, 5.8153)
  line L151 (8.5297, 5.8153) -> (8.5297, 6.0706)
  line L152 (8.5297, 6.0706) -> (9.4981, 6.0706)
  line L153 (9.4981, 6.0706) -> (9.4981, 5.8153)
  line L154 (9.4981, 5.8153) -> (9.18, 5.8153)
  line L155 (9.18, 5.8153) -> (9.18, 3.8259)
  line L156 (9.18, 3.8259) -> (9.4981, 3.8259)
  line L157 (9.4981, 3.8259) -> (9.4981, 3.5706)
  line L158 (10.4928, 3.5706) -> (10.4928, 5.7748)
  line L159 (10.4928, 5.7748) -> (9.6541, 5.7748)
  line L160 (9.6541, 5.7748) -> (9.6541, 6.0706)
  line L161 (9.6541, 6.0706) -> (11.6638, 6.0706)
  line L162 (11.6638, 6.0706) -> (11.6638, 5.7748)
  line L163 (11.6638, 5.7748) -> (10.8251, 5.7748)
  line L164 (10.8251, 5.7748) -> (10.8251, 3.5706)
  line L165 (10.8251, 3.5706) -> (10.4928, 3.5706)
  line L166 (11.6476, 3.5706) -> (12.4904, 6.0706)
  line L167 (12.4904, 6.0706) -> (12.8997, 6.0706)
  line L168 (12.8997, 6.0706) -> (13.7424, 3.5706)
  line L169 (13.7424, 3.5706) -> (13.392, 3.5706)
  line L170 (13.392, 3.5706) -> (13.165, 4.2695)
  line L171 (13.165, 4.2695) -> (12.2108, 4.2695)
  line L172 (12.2108, 4.2695) -> (11.9839, 3.5706)
  line L173 (11.9839, 3.5706) -> (11.6476, 3.5706)
  line L174 (13.0739, 4.5532) -> (12.6869, 5.7302)
  line L175 (12.6869, 5.7302) -> (12.302, 4.5532)
  line L176 (12.302, 4.5532) -> (13.0739, 4.5532)
  line L177 (15.428, 3.5706) -> (13.9795, 3.5706)
  line L178 (13.9795, 3.5706) -> (13.9795, 6.0706)
  line L179 (13.9795, 6.0706) -> (14.3117, 6.0706)
  line L180 (14.3117, 6.0706) -> (14.3117, 3.8664)
  line L181 (14.3117, 3.8664) -> (15.428, 3.8664)
  line L182 (15.428, 3.8664) -> (15.428, 3.5706)
  spline S181 degree 2 poles (17.46, 3.526) (17.1886, 3.526) (16.8077, 3.6395) (16.6395, 3.7205) knots 0 0 0 1 2 2 2
  line L183 (16.6395, 3.7205) -> (16.6395, 4.1379)
  line L184 (16.6395, 4.1379) -> (16.6638, 4.1379)
  spline S182 degree 2 poles (16.6638, 4.1379) (16.8279, 3.9839) (17.2433, 3.8137) (17.4357, 3.8137) knots 0 0 0 1 2 2 2
  spline S183 degree 2 poles (17.4357, 3.8137) (17.7112, 3.8137) (17.9928, 4.0426) (17.9928, 4.231) knots 0 0 0 1 2 2 2
  spline S184 degree 2 poles (17.9928, 4.231) (17.9928, 4.381) (17.845, 4.5674) (17.6849, 4.6139) knots 0 0 0 1 2 2 2
  spline S185 degree 2 poles (17.6849, 4.6139) (17.5694, 4.6464) (17.377, 4.6909) (17.2331, 4.7274) knots 0 0 0 1 2 2 2
  spline S186 degree 2 poles (17.2331, 4.7274) (17.1035, 4.7618) (16.8988, 4.8652) (16.8198, 4.9482) knots 0 0 0 1 2 2 2
  spline S187 degree 2 poles (16.8198, 4.9482) (16.7428, 5.0313) (16.6578, 5.2541) (16.6578, 5.4) knots 0 0 0 1 2 2 2
  spline S188 degree 2 poles (16.6578, 5.4) (16.6578, 5.7039) (17.1318, 6.1152) (17.4985, 6.1152) knots 0 0 0 1 2 2 2
  spline S189 degree 2 poles (17.4985, 6.1152) (17.7092, 6.1152) (18.082, 6.0321) (18.242, 5.9531) knots 0 0 0 1 2 2 2
  line L185 (18.242, 5.9531) -> (18.242, 5.556)
  line L186 (18.242, 5.556) -> (18.2177, 5.556)
  spline S190 degree 2 poles (18.2177, 5.556) (18.0982, 5.6654) (17.7254, 5.8275) (17.5208, 5.8275) knots 0 0 0 1 2 2 2
  spline S191 degree 2 poles (17.5208, 5.8275) (17.2898, 5.8275) (17.0042, 5.6107) (17.0042, 5.4344) knots 0 0 0 1 2 2 2
  spline S192 degree 2 poles (17.0042, 5.4344) (17.0042, 5.2764) (17.1723, 5.088) (17.3304, 5.0455) knots 0 0 0 1 2 2 2
  spline S193 degree 2 poles (17.3304, 5.0455) (17.4357, 5.0171) (17.7416, 4.9442) (17.8429, 4.9138) knots 0 0 0 1 2 2 2
  spline S194 degree 2 poles (17.8429, 4.9138) (18.1002, 4.8348) (18.3393, 4.5167) (18.3393, 4.2837) knots 0 0 0 1 2 2 2
  spline S195 degree 2 poles (18.3393, 4.2837) (18.3393, 4.1358) (18.2197, 3.8522) (18.1124, 3.7529) knots 0 0 0 1 2 2 2
  spline S196 degree 2 poles (18.1124, 3.7529) (17.9928, 3.6435) (17.689, 3.526) (17.46, 3.526) knots 0 0 0 1 2 2 2
  line L187 (18.6776, 3.5706) -> (18.6776, 6.0706)
  line L188 (18.6776, 6.0706) -> (20.2416, 6.0706)
  line L189 (20.2416, 6.0706) -> (20.2416, 5.7748)
  line L190 (20.2416, 5.7748) -> (19.0099, 5.7748)
  line L191 (19.0099, 5.7748) -> (19.0099, 5.09)
  line L192 (19.0099, 5.09) -> (20.1586, 5.09)
  line L193 (20.1586, 5.09) -> (20.1586, 4.7943)
  line L194 (20.1586, 4.7943) -> (19.0099, 4.7943)
  line L195 (19.0099, 4.7943) -> (19.0099, 3.8664)
  line L196 (19.0099, 3.8664) -> (20.2416, 3.8664)
  line L197 (20.2416, 3.8664) -> (20.2416, 3.5706)
  line L198 (20.2416, 3.5706) -> (18.6776, 3.5706)
  line L199 (22.5411, 3.5706) -> (22.1095, 3.5706)
  line L200 (22.1095, 3.5706) -> (21.3194, 4.5653)
  line L201 (21.3194, 4.5653) -> (20.9386, 4.5653)
  line L202 (20.9386, 4.5653) -> (20.9386, 3.5706)
  line L203 (20.9386, 3.5706) -> (20.6063, 3.5706)
  line L204 (20.6063, 3.5706) -> (20.6063, 6.0706)
  line L205 (20.6063, 6.0706) -> (21.2505, 6.0706)
  spline S197 degree 2 poles (21.2505, 6.0706) (21.4653, 6.0706) (21.755, 6.024) (21.8867, 5.9389) knots 0 0 0 1 2 2 2
  spline S198 degree 2 poles (21.8867, 5.9389) (22.0184, 5.8538) (22.1703, 5.5884) (22.1703, 5.3919) knots 0 0 0 1 2 2 2
  spline S199 degree 2 poles (22.1703, 5.3919) (22.1703, 5.1184) (21.8907, 4.7477) (21.6517, 4.6585) knots 0 0 0 1 2 2 2
  line L206 (21.6517, 4.6585) -> (22.5411, 3.5706)
  spline S200 degree 2 poles (21.8239, 5.3656) (21.8239, 5.475) (21.7469, 5.6431) (21.6659, 5.6978) knots 0 0 0 1 2 2 2
  spline S201 degree 2 poles (21.6659, 5.6978) (21.595, 5.7444) (21.4065, 5.7829) (21.2688, 5.7829) knots 0 0 0 1 2 2 2
  line L207 (21.2688, 5.7829) -> (20.9386, 5.7829)
  line L208 (20.9386, 5.7829) -> (20.9386, 4.8429)
  line L209 (20.9386, 4.8429) -> (21.2303, 4.8429)
  spline S202 degree 2 poles (21.2303, 4.8429) (21.3741, 4.8429) (21.6031, 4.8935) (21.6821, 4.9725) knots 0 0 0 1 2 2 2
  spline S203 degree 2 poles (21.6821, 4.9725) (21.755, 5.0414) (21.8239, 5.2359) (21.8239, 5.3656) knots 0 0 0 1 2 2 2
  line L210 (24.5528, 6.0706) -> (23.6918, 3.5706)
  line L211 (23.6918, 3.5706) -> (23.3332, 3.5706)
  line L212 (23.3332, 3.5706) -> (22.4722, 6.0706)
  line L213 (22.4722, 6.0706) -> (22.8287, 6.0706)
  line L214 (22.8287, 6.0706) -> (23.5216, 3.994)
  line L215 (23.5216, 3.994) -> (24.2145, 6.0706)
  line L216 (24.2145, 6.0706) -> (24.5528, 6.0706)
  spline S204 degree 2 poles (26.5605, 5.7849) (26.7023, 5.6188) (26.8603, 5.1326) (26.8603, 4.8206) knots 0 0 0 1 2 2 2
  spline S205 degree 2 poles (26.8603, 4.8206) (26.8603, 4.5167) (26.7064, 4.0244) (26.5605, 3.8583) knots 0 0 0 1 2 2 2
  spline S206 degree 2 poles (26.5605, 3.8583) (26.4065, 3.684) (25.9993, 3.5179) (25.7542, 3.5179) knots 0 0 0 1 2 2 2
  spline S207 degree 2 poles (25.7542, 3.5179) (25.5009, 3.5179) (25.0958, 3.6901) (24.9479, 3.8583) knots 0 0 0 1 2 2 2
  spline S208 degree 2 poles (24.9479, 3.8583) (24.804, 4.0244) (24.6501, 4.5127) (24.6501, 4.8206) knots 0 0 0 1 2 2 2
  spline S209 degree 2 poles (24.6501, 4.8206) (24.6501, 5.1346) (24.8061, 5.6127) (24.9499, 5.7849) knots 0 0 0 1 2 2 2
  spline S210 degree 2 poles (24.9499, 5.7849) (25.0958, 5.9511) (25.503, 6.1233) (25.7542, 6.1233) knots 0 0 0 1 2 2 2
  spline S211 degree 2 poles (25.7542, 6.1233) (26.0095, 6.1233) (26.4187, 5.945) (26.5605, 5.7849) knots 0 0 0 1 2 2 2
  spline S212 degree 2 poles (26.5139, 4.8206) (26.5139, 5.0678) (26.4065, 5.4507) (26.3093, 5.5763) knots 0 0 0 1 2 2 2
  spline S213 degree 2 poles (26.3093, 5.5763) (26.21, 5.7059) (25.9304, 5.8356) (25.7562, 5.8356) knots 0 0 0 1 2 2 2
  spline S214 degree 2 poles (25.7562, 5.8356) (25.5759, 5.8356) (25.3044, 5.71) (25.2011, 5.5763) knots 0 0 0 1 2 2 2
  spline S215 degree 2 poles (25.2011, 5.5763) (25.1018, 5.4486) (24.9965, 5.0637) (24.9965, 4.8206) knots 0 0 0 1 2 2 2
  spline S216 degree 2 poles (24.9965, 4.8206) (24.9965, 4.3283) (25.4098, 3.8056) (25.7562, 3.8056) knots 0 0 0 1 2 2 2
  spline S217 degree 2 poles (25.7562, 3.8056) (26.1027, 3.8056) (26.5139, 4.3283) (26.5139, 4.8206) knots 0 0 0 1 2 2 2
  point P0 (0, 0)
  point P1 (4.5761, 36.1398)
  point P2 (4.7521, 34.2037)
  constraints: 4 other
emboss "엠보싱1" sketch "스케치5" operation cut depth 0.1 direction (0, 0, 1)
sketch "스케치6" plane through (-40, 0, -20) normal (-1, 0, 0) x (0, 0, 1)
  line L0 (6.5, 7.5) -> (13.5, 7.5)
  line L1 (13.5, 7.5) -> (13.5, 3.5)
  line L2 (13.5, 3.5) -> (6.5, 3.5)
  line L3 (6.5, 3.5) -> (6.5, 7.5)
  line L4 (0, 0) -> (20, 0) projected
  point P0 (10, 3.5)
  point P1 (10, 0)
  dimension "d41" = 4
  dimension "d42" = 7.5
  dimension "d43" = 7
  constraints: 8 end point, 2 midpoint, 2 parallel, 1 horizontal, 1 perpendicular, 1 vertical alignment
  measures "d41" distance of L2.end L0.start
  measures "d42" distance between parallel lines of L4 L0
  measures "d43" distance of L0.start L0.end
extrude "돌출6" add sketch "스케치6" along normal blind 3
chamfer "모따기1" distance 0.5 distance2 2 4 edges at (-43, 5.5, -13.5) (-43, 7.5, -10) (-43, 5.5, -6.5) (-43, 3.5, -10) measured on face at (-43, 7, -10) measured on face at (-43, 5.5, -7) measured on face at (-43, 4, -10) measured on face at (-43, 5.5, -13)
sketch "스케치7" plane through (-43, 0, -20) normal (-1, 0, 0) x (0, 0, 1)
  circle A0 centre (8.5, 5.5) radius 0.75
  circle A1 centre (11.5, 5.5) radius 0.75
  circle A2 centre (10, 5.5) radius 0.75
  line L0 (8.5, 5.5) -> (11.5, 5.5) construction
  line L1 (7, 7) -> (13, 7) construction
  line L2 (7, 4) -> (7, 7) construction
  point P0 (20, 0)
  point P1 (10, 7)
  point P2 (7, 5.5)
  point P3 (10.75, 5.5)
  point P4 (9.25, 5.5)
  dimension "d49" = 1.5
  dimension "d50" = 1.5
  dimension "d51" = 1.5
  constraints: 4 midpoint, 3 centre point, 2 end point, 2 equal radius, 1 horizontal, 1 horizontal alignment, 1 vertical alignment
  measures "d49" diameter of A0
  measures "d50" diameter of A1
  measures "d51" diameter of A2
extrude "돌출7" add sketch "스케치7" along normal blind 5
fillet "모깎기2" radius 1 8 edges at (-40, 13.65, -20) (-40, 35.5, -20) (0, 13.65, -20) (0, 35.5, -20) (-40, 13.65, 0) (-40, 35.5, 0) (0, 13.65, 0) (0, 35.5, 0)
chamfer "모따기2" distance 0.5 angle 45 17 edges at (-20, 40.5, 0) (-0.2929, 40.5, -0.2929) (0, 40.5, -10) (-0.2929, 40.5, -19.7071) (-20, 40.5, -20) (-39.7071, 40.5, -19.7071) (-40, 40.5, -10) (-39.7071, 40.5, -0.2929) (-20, 0, 0) (-0.2929, 0, -0.2929) (0, 0, -10) (-0.2929, 0, -19.7071) (-20, 0, -20) (-39.7071, 0, -19.7071) (-40, 0, -10) (-39.7071, 0, -0.2929) (-36.7, 41.7, -10)
chamfer "모따기4" distance 0.5 angle 45 1 edges at (-33.2, 45.5, -10)